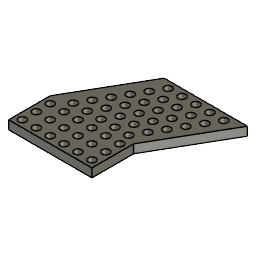
mounting-bracket (Autodesk Fusion 360 design; units mm, degrees)
part number: 2026-10-17-20-34-59-692
Autodesk Fusion 360 part; units mm, degrees
sketch "bracket body" plane through (0, 0, 0) normal (0, 0, 1) x (1, 0, 0)
  line L0 (0, 0) -> (48, 0)
  line L1 (48, 0) -> (48, 24)
  line L2 (48, 24) -> (0, 24)
  line L3 (0, 24) -> (0, 0)
  line L4 (48, 24) -> (72, 65.5692)
  line L5 (0, 24) -> (24, 65.5692)
  line L6 (24, 65.5692) -> (72, 65.5692)
  dimension "d3" = 48
  dimension "d4" = 24
  dimension "d6" = 120
  dimension "d7" = 48
  constraint horizontal L0
  constraint vertical L1
  constraint horizontal L2
  constraint vertical L3
  constraint coincident L0.start L3.end
  constraint parallel L4 L5
  constraint equal L4 L5
  measures "d3" distance of L1.end L2.end
  measures "d4" distance of L0.end L1.end
  measures "d6" angle of L2 L4
  measures "d7" distance of L1.end L4.end
extrude "Extrude1" add sketch "bracket body" along normal blind 5
sketch "top hole" plane through (0, 0, 5) normal (0, 0, 1) x (-1, 0, 0)
  line L0 (0, -24) -> (0, 0)
  line L1 (0, 0) -> (-48, 0)
  line L2 (-48, 0) -> (-48, -24)
  line L3 (-48, -24) -> (-72, -65.5692)
  line L4 (-72, -65.5692) -> (-24, -65.5692)
  line L5 (-24, -65.5692) -> (0, -24)
  line L6 (0, 0) -> (-4, 0) construction
  line L7 (-4, 0) -> (-4, -4) construction
  line L8 (-4, -4) -> (0, -4) construction
  line L9 (0, -4) -> (0, 0) construction
  circle A0 centre (-4, -4) radius 2.15
  dimension "d8" = 4
  dimension "d9" = 4
  dimension "d10" = 4.3
  constraint horizontal L6
  constraint vertical L7
  constraint horizontal L8
  constraint vertical L9
  constraint coincident L0.end L1.start
  constraint coincident L7.end L8.start
  measures "d8" distance of L0.end L6.end
  measures "d9" distance of L0.end L8.end
  measures "d10" diameter of A0
extrude "Extrude2" cut sketch "top hole" against normal up to surface (5 mm away) contours A0
pattern_linear "R-Pattern1" count 3 spacing 8 along (0, 1, 0) count 6 spacing 8 along (1, 0, 0) of "Extrude2"
sketch "angle hole" plane through (0, 0, 5) normal (0, 0, 1) x (-1, 0, 0)
  circle A0 centre (-44, -20) radius 2.15
  circle A1 centre (-44, -12) radius 2.15
  circle A2 centre (-44, -4) radius 2.15
  circle A3 centre (-36, -20) radius 2.15
  circle A4 centre (-36, -12) radius 2.15
  circle A5 centre (-36, -4) radius 2.15
  circle A6 centre (-28, -20) radius 2.15
  circle A7 centre (-28, -12) radius 2.15
  circle A8 centre (-28, -4) radius 2.15
  circle A9 centre (-20, -20) radius 2.15
  circle A10 centre (-20, -12) radius 2.15
  circle A11 centre (-20, -4) radius 2.15
  circle A12 centre (-12, -20) radius 2.15
  circle A13 centre (-12, -12) radius 2.15
  circle A14 centre (-12, -4) radius 2.15
  circle A15 centre (-4, -20) radius 2.15
  circle A16 centre (-4, -12) radius 2.15
  circle A17 centre (-4, -4) radius 2.15
  line L0 (0, -24) -> (0, 0)
  line L1 (0, 0) -> (-48, 0)
  line L2 (-48, 0) -> (-48, -24)
  line L3 (-48, -24) -> (-72, -65.5692)
  line L4 (-72, -65.5692) -> (-24, -65.5692)
  line L5 (-24, -65.5692) -> (0, -24)
  line L6 (-4, -22.9282) -> (-4, -4) construction
  line L7 (-4, -4) -> (-44, -4) construction
  line L8 (-44, -4) -> (-44, -25.0718) construction
  line L9 (-44, -25.0718) -> (-65.0718, -61.5692) construction
  circle A18 centre (-30.3509, -61.5692) radius 2.15
  dimension "d18" = -4
  dimension "d19" = 4.3
  dimension "d26" = 4
  dimension "d27" = 7.5
  measures "d19" diameter of A18
  measures "d26" distance of L4 A18.centre
  measures "d27" distance of L5 A18.centre
extrude "Extrude3" cut sketch "angle hole" against normal blind 5 contours A18
pattern_linear "R-Pattern2" count 5 spacing 8 along (1, 0, 0) count 6 spacing 8 along (-0.5, -0.866025, 0) of "Extrude3"
named bodies: "main bracket"
